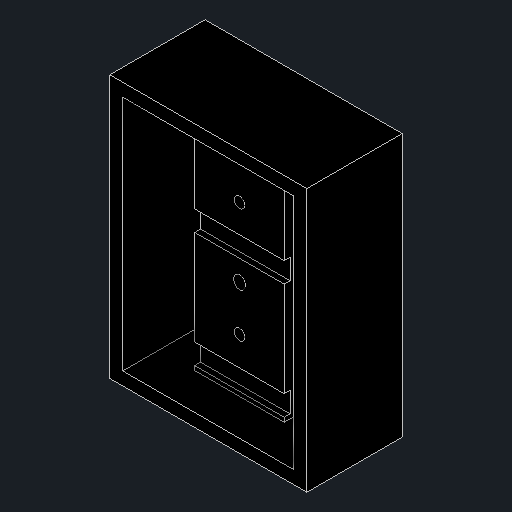
# Autodesk Inventor part: Optical Module d1.2
Saved by Autodesk Inventor 2027.2 (Build 312334000, 334)
## iProperties
Created: 2026-11-11
Part Number: Optical Module d1.2
Material: Generic
Description: Optical module: pocket for both breakouts, solid optical block with an aimed view bore (aperture 1.2 mm) and an LED bore per sensor
Document SubType Name: Modeling
Designer: isaac
Density: 1 g/cm^3
Appearance: Black
Author: isaac
Autodesk Inventor part; units mm, degrees
ref_plane "Work Plane1" through (0, 0, -14.9) normal (0, 0, 1) x (1, 0, 0)
sketch "Sketch1" plane through (0, 0, -14.9) normal (0, 0, 1) x (1, 0, 0)
  line L0 (55.2, 5.83) -> (85.6, 5.83)
  line L1 (85.6, 5.83) -> (85.6, 46.39)
  line L2 (85.6, 46.39) -> (55.2, 46.39)
  line L3 (55.2, 46.39) -> (55.2, 5.83)
  constraints: 8 end point, 2 parallel, 1 horizontal, 1 perpendicular
extrude "Body" add sketch "Sketch1" along normal blind 14.7
ref_plane "Work Plane2" through (0, 0, -13.4) normal (0, 0, 1) x (1, 0, 0)
sketch "Sketch2" plane through (0, 0, -13.4) normal (0, 0, 1) x (1, 0, 0)
  line L0 (57.2, 7.83) -> (83.6, 7.83)
  line L1 (83.6, 7.83) -> (83.6, 44.39)
  line L2 (83.6, 44.39) -> (57.2, 44.39)
  line L3 (57.2, 44.39) -> (57.2, 7.83)
  constraints: 8 end point, 2 parallel, 1 horizontal, 1 perpendicular
extrude "Sensor pocket" cut sketch "Sketch2" along normal blind 13.2
ref_plane "Work Plane3" through (0, 0, -13.4) normal (0, 0, 1) x (1, 0, 0)
sketch "Sketch3" plane through (0, 0, -13.4) normal (0, 0, 1) x (1, 0, 0)
  line L0 (63.5, 8.63) -> (77.3, 8.63)
  line L1 (77.3, 8.63) -> (77.3, 43.59)
  line L2 (77.3, 43.59) -> (63.5, 43.59)
  line L3 (63.5, 43.59) -> (63.5, 8.63)
  constraints: 8 end point, 2 parallel, 1 horizontal, 1 perpendicular
extrude "Optical block" add sketch "Sketch3" along normal blind 8.4
ref_plane "Work Plane4" through (0, 0, -5.9) normal (0, 0, 1) x (1, 0, 0)
sketch "Sketch4" plane through (0, 0, -5.9) normal (0, 0, 1) x (1, 0, 0)
  line L0 (63, 27.08) -> (77.8, 27.08)
  line L1 (77.8, 27.08) -> (77.8, 30.22)
  line L2 (77.8, 30.22) -> (63, 30.22)
  line L3 (63, 30.22) -> (63, 27.08)
  line L4 (63, 9.3) -> (77.8, 9.3)
  line L5 (77.8, 9.3) -> (77.8, 12.44)
  line L6 (77.8, 12.44) -> (63, 12.44)
  line L7 (63, 12.44) -> (63, 9.3)
  constraints: 16 end point, 4 parallel, 2 horizontal, 2 perpendicular
extrude "Header pin recesses" cut sketch "Sketch4" along normal blind 1
ref_plane "Work Plane5" through (0, 0, -14.9) normal (0, 0, 1) x (1, 0, 0)
sketch "Sketch5" plane through (0, 0, -14.9) normal (0, 0, 1) x (1, 0, 0)
  line L0 (66.4, 16) -> (74.4, 16)
  line L1 (74.4, 16) -> (74.4, 25.61)
  line L2 (74.4, 25.61) -> (66.4, 25.61)
  line L3 (66.4, 25.61) -> (66.4, 16)
  line L4 (66.4, 26.61) -> (74.4, 26.61)
  line L5 (74.4, 26.61) -> (74.4, 37)
  line L6 (74.4, 37) -> (66.4, 37)
  line L7 (66.4, 37) -> (66.4, 26.61)
  constraints: 16 end point, 4 parallel, 2 horizontal, 2 perpendicular
extrude "Read chamber" cut sketch "Sketch5" along normal blind 2.9
sketch3d "3D Sketch1"
ref_plane "Work Plane6" through (70.4, 32.7117, -11.25) normal (0, -0.2817, -0.9595) x (1, 0, 0)
sketch "Sketch6" plane through (70.4, 32.7117, -11.25) normal (0, -0.2817, -0.9595) x (1, 0, 0)
  circle A0 centre (0, 0) radius 0.6
  constraints: 1 centre point
extrude "Aperture TCS3448" cut sketch "Sketch6" along normal mid plane 1.7717
sketch3d "3D Sketch2"
ref_plane "Work Plane7" through (70.4, 33.8126, -7.5) normal (0, -0.2817, -0.9595) x (1, 0, 0)
sketch "Sketch7" plane through (70.4, 33.8126, -7.5) normal (0, -0.2817, -0.9595) x (1, 0, 0)
  circle A0 centre (0, 0) radius 0.8
  constraints: 1 centre point
extrude "View bore TCS3448" cut sketch "Sketch7" along normal mid plane 6.2532
ref_plane "Work Plane8" through (0, 0, -12) normal (0, 0, 1) x (1, 0, 0)
sketch "Sketch8" plane through (0, 0, -12) normal (0, 0, 1) x (1, 0, 0)
  line L0 (68.9, 33.9572) -> (71.9, 33.9572)
  line L1 (71.9, 33.9572) -> (71.9, 36.1572)
  line L2 (71.9, 36.1572) -> (68.9, 36.1572)
  line L3 (68.9, 36.1572) -> (68.9, 33.9572)
  constraints: 8 end point, 2 parallel, 1 horizontal, 1 perpendicular
extrude "LED slot TCS3448" cut sketch "Sketch8" along normal blind 1.5
sketch3d "3D Sketch3"
ref_plane "Work Plane9" through (70.4, 38.5236, -7.425) normal (0, -0.7481, -0.6636) x (1, 0, 0)
sketch "Sketch9" plane through (70.4, 38.5236, -7.425) normal (0, -0.7481, -0.6636) x (1, 0, 0)
  circle A0 centre (0, 0) radius 0.9
  constraints: 1 centre point
extrude "LED bore TCS3448" cut sketch "Sketch9" along normal mid plane 9.2675
sketch3d "3D Sketch4"
ref_plane "Work Plane10" through (70.4, 18.7483, -11.25) normal (0, 0.2817, -0.9595) x (-1, 0, 0)
sketch "Sketch10" plane through (70.4, 18.7483, -11.25) normal (0, 0.2817, -0.9595) x (-1, 0, 0)
  circle A0 centre (0, 0) radius 0.6
  constraints: 1 centre point
extrude "Aperture AS7343" cut sketch "Sketch10" along normal mid plane 1.7717
sketch3d "3D Sketch5"
ref_plane "Work Plane11" through (70.4, 17.6474, -7.5) normal (0, 0.2817, -0.9595) x (-1, 0, 0)
sketch "Sketch11" plane through (70.4, 17.6474, -7.5) normal (0, 0.2817, -0.9595) x (-1, 0, 0)
  circle A0 centre (0, 0) radius 0.8
  constraints: 1 centre point
extrude "View bore AS7343" cut sketch "Sketch11" along normal mid plane 6.2532
ref_plane "Work Plane12" through (0, 0, -12) normal (0, 0, 1) x (1, 0, 0)
sketch "Sketch12" plane through (0, 0, -12) normal (0, 0, 1) x (1, 0, 0)
  line L0 (68.9, 19.9938) -> (71.9, 19.9938)
  line L1 (71.9, 19.9938) -> (71.9, 22.1938)
  line L2 (71.9, 22.1938) -> (68.9, 22.1938)
  line L3 (68.9, 22.1938) -> (68.9, 19.9938)
  constraints: 8 end point, 2 parallel, 1 horizontal, 1 perpendicular
extrude "LED slot AS7343" cut sketch "Sketch12" along normal blind 1.5
sketch3d "3D Sketch6"
ref_plane "Work Plane13" through (70.4, 22.6519, -7.425) normal (0, -0.452, -0.892) x (1, 0, 0)
sketch "Sketch13" plane through (70.4, 22.6519, -7.425) normal (0, -0.452, -0.892) x (1, 0, 0)
  circle A0 centre (0, 0) radius 0.9
  constraints: 1 centre point
extrude "LED bore AS7343" cut sketch "Sketch13" along normal mid plane 6.8944
body "Solid1"
